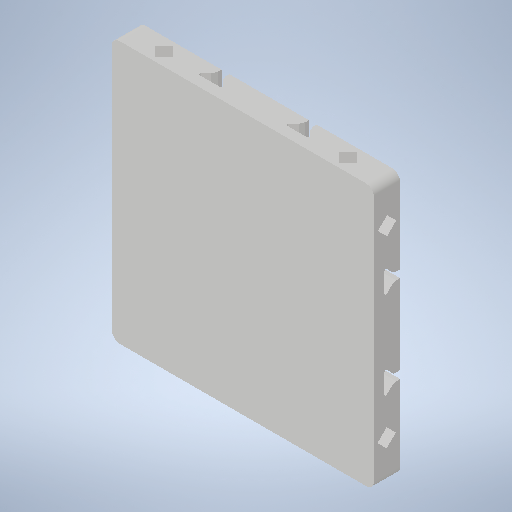
# Autodesk Inventor part: Main
Saved by Autodesk Inventor 2025.2 (Build 292293000, 293)
## iProperties
Created: 2026-02-04
Part Number: Main
Material: Generic
Document SubType Name: Modeling
Designer: crazi
Density: 1 g/cm^3
Appearance: Default
Author: crazi
Autodesk Inventor part; units mm, degrees
ref_plane "YZ Plane" through (0, 0, 0) normal (1, 0, 0) x (0, 1, 0)
sketch "Sketch1" plane through (0, 0, 0) normal (0, 0, 1) x (1, 0, 0)
  line L0 (0, 0) -> (100, 0)
  line L1 (100, 0) -> (100, -100)
  line L2 (100, -100) -> (0, -100)
  line L3 (0, -100) -> (0, 0)
  dimension "d0" = 100
  dimension "d1" = 100
  constraints: 8 end point, 2 parallel, 1 horizontal, 1 perpendicular
  measures "d0" distance of L1.end L2.end
  measures "d1" distance of L0.end L1.end
extrude "Extrusion1" add sketch "Sketch1" along normal blind 10
sketch "Sketch2" plane through (0, 0, 0) normal (0, 1, 0) x (1, 0, 0)
  line L0 (66.66, -6) -> (61.66, -6)
  line L1 (66.66, -6) -> (71.66, -6)
  line L2 (71.66, -6) -> (68.1245, -2.4645)
  line L3 (68.1245, -2.4645) -> (68.1245, 0)
  line L4 (61.66, -6) -> (65.1955, -2.4645)
  line L5 (61.66, -6) -> (66.66, -6) construction
  line L6 (65.1955, -2.4645) -> (65.1955, 0)
  line L7 (65.1955, 0) -> (68.1245, 0)
  line L8 (33.33, -6) -> (38.33, -6)
  line L9 (33.33, -6) -> (28.33, -6)
  line L10 (28.33, -6) -> (31.8655, -2.4645)
  line L11 (31.8655, -2.4645) -> (31.8655, 0)
  line L12 (38.33, -6) -> (34.7945, -2.4645)
  line L13 (38.33, -6) -> (43.33, -6) construction
  line L14 (34.7945, -2.4645) -> (34.7945, 0)
  line L15 (31.8655, 0) -> (34.7945, 0)
  line L16 (0, 0) -> (100, 0) projected
  dimension "d7" = 5
  dimension "d8" = 5
  dimension "d9" = 5
  dimension "d10" = 45
  dimension "d11" = 5
  dimension "d12" = 45
  dimension "d13" = 5
  dimension "d14" = 5
  dimension "d15" = 5
  dimension "d16" = 45
  dimension "d17" = 5
  dimension "d18" = 135
  constraints: 32 end point, 4 horizontal, 2 equal length, 2 perpendicular, 1 collinear
  measures "d7" distance of L0.start L0.end
  measures "d8" distance of L0.start L1.end
  measures "d9" distance of L1.end L2.end
  measures "d10" angle of L2 L1
  measures "d11" distance of L0.end L4.end
  measures "d12" angle of L5 L4
  measures "d13" distance of L8.start L8.end
  measures "d14" distance of L8.start L9.end
  measures "d15" distance of L9.end L10.end
  measures "d16" angle of L9 L10
  measures "d17" distance of L8.end L12.end
  measures "d18" angle of L13 L12
extrude "Extrusion2" cut sketch "Sketch2" against normal up to surface (100 mm away)
sketch "Sketch3" plane through (0, -100, 0) normal (-1, 0, 0) x (0, 0, 1)
  line L0 (0, 0) -> (2.4645, 0) projected
  line L1 (6, 33.33) -> (6, 38.33)
  line L2 (6, 33.33) -> (6, 28.33)
  line L3 (6, 28.33) -> (2.4645, 31.8655)
  line L4 (2.4645, 31.8655) -> (0, 31.8655)
  line L5 (6, 38.33) -> (2.4645, 34.7945)
  line L6 (6, 38.33) -> (11, 38.33) construction
  line L7 (2.4645, 34.7945) -> (0, 34.7945)
  line L8 (0, 31.8655) -> (0, 34.7945)
  line L9 (6, 66.66) -> (6, 61.66)
  line L10 (6, 61.66) -> (2.4645, 65.1955)
  line L11 (2.4645, 65.1955) -> (0, 65.1955)
  line L12 (6, 66.66) -> (6, 71.66)
  line L13 (6, 71.66) -> (2.4645, 68.1245)
  line L14 (2.4645, 68.1245) -> (0, 68.1245)
  line L15 (0, 65.1955) -> (0, 68.1245)
  point P0 (1.4645, 0)
  dimension "d30" = 5
  dimension "d31" = 5
  dimension "d32" = 5
  dimension "d33" = 45
  dimension "d34" = 5
  dimension "d35" = 135
  dimension "d36" = 5
  dimension "d37" = 5
  dimension "d38" = 45
  dimension "d39" = 5
  dimension "d40" = 5
  dimension "d41" = 45
  constraints: 30 end point, 1 equal length, 1 horizontal, 1 perpendicular
  measures "d30" distance of L1.start L1.end
  measures "d31" distance of L1.start L2.end
  measures "d32" distance of L2.end L3.end
  measures "d33" angle of L2 L3
  measures "d34" distance of L1.end L5.end
  measures "d35" angle of L5 L6
  measures "d36" distance of L9.start L9.end
  measures "d37" distance of L9.end L10.end
  measures "d38" angle of L9 L10
  measures "d39" distance of L9.start L12.end
  measures "d40" distance of L12.end L13.end
  measures "d41" angle of L13 L12
chamfer "Chamfer2" distance 1 angle 45 4 edges at (34.7945, -50, 2.4645) (68.1245, -50, 2.4645) (65.1955, -50, 2.4645) (31.8655, -50, 2.4645)
fillet "Fillet3" radius 0.5 4 edges at (28.33, -50, 6) (38.33, -50, 6) (71.66, -50, 6) (61.66, -50, 6)
extrude "Extrusion3" cut sketch "Sketch3" against normal up to surface (100 mm away)
chamfer "Chamfer3" distance 1 angle 45 11 edges at (15.7257, -34.8045, 2.4645) (15.7257, -68.1345, 2.4645) (15.7257, -65.2055, 2.4645) (15.7257, -31.8755, 2.4645) (84.2693, -34.8045, 2.4645) (84.2693, -68.1345, 2.4645) (49.995, -31.8755, 2.4645) (49.995, -68.1345, 2.4645) (49.995, -65.2055, 2.4645) (49.995, -34.8045, 2.4645) (84.2693, -31.8755, 2.4645)
fillet "Fillet4" radius 0.5 6 edges at (14.7686, -71.67, 6) (14.7686, -61.67, 6) (14.7686, -28.34, 6) (14.7686, -38.34, 6) (85.2264, -38.34, 6) (85.2264, -28.34, 6)
fillet "Fillet5" radius 0.5 6 edges at (85.2264, -71.67, 6) (85.2264, -61.67, 6) (49.995, -38.34, 6) (49.995, -28.34, 6) (49.995, -71.67, 6) (49.995, -61.67, 6)
sketch "Sketch4" plane through (0, -100, 10) normal (0, -1, 0) x (1, 0, 0)
  line L0 (85, -1.5) -> (88.5, -5)
  line L1 (88.5, -5) -> (85, -8.5)
  line L2 (85, -8.5) -> (81.5, -5)
  line L3 (81.5, -5) -> (85, -1.5)
  line L4 (15, -1.5) -> (18.5, -5)
  line L5 (18.5, -5) -> (15, -8.5)
  line L6 (15, -8.5) -> (11.5, -5)
  line L7 (11.5, -5) -> (15, -1.5)
  point P0 (0, -10)
  point P1 (15, -5)
  point P2 (100, -10)
  point P3 (85, -5)
  point P4 (85, -5)
  point P5 (15, -5)
  constraints: 16 end point, 2 coincident, 18 other
extrude "Extrusion4" cut sketch "Sketch4" against normal blind 11
sketch "Sketch5" plane through (100, -100, 10) normal (1, 0, 0) x (0, 0, -1)
  line L0 (1.3536, 15) -> (4.8536, 18.5)
  line L1 (4.8536, 18.5) -> (8.3536, 15)
  line L2 (8.3536, 15) -> (4.8536, 11.5)
  line L3 (4.8536, 11.5) -> (1.3536, 15)
  line L4 (1.5, 85) -> (5, 88.5)
  line L5 (5, 88.5) -> (8.5, 85)
  line L6 (8.5, 85) -> (5, 81.5)
  line L7 (5, 81.5) -> (1.5, 85)
  point P0 (0, 0)
  point P1 (4.8536, 15)
  point P2 (5, 85)
  point P3 (4.8536, 15)
  point P4 (5, 85)
  constraints: 16 end point, 2 coincident, 18 other
extrude "Extrusion5" cut sketch "Sketch5" against normal blind 11
ref_plane "Work Plane1" through (50, -100, 10) normal (-1, 0, 0) x (0, 0, 1)
ref_plane "Work Plane2" through (0, -50, 10) normal (0, -1, 0) x (1, 0, 0)
mirror "Mirror1" about plane through (0, -50, 10) normal (0, -1, 0) of "Extrusion4"
mirror "Mirror2" about plane through (50, -100, 10) normal (-1, 0, 0) of "Extrusion5"
chamfer "Chamfer4" distance 1 angle 45 32 edges at (86.75, -89, 6.75) (86.75, -89, 3.25) (83.25, -89, 3.25) (83.25, -89, 6.75) (13.25, -89, 3.25) (13.25, -89, 6.75) (16.75, -89, 3.25) (16.75, -89, 6.75) (13.25, -11, 3.25) (13.25, -11, 6.75) (16.75, -11, 3.25) (16.75, -11, 6.75) (83.25, -11, 3.25) (83.25, -11, 6.75) (86.75, -11, 6.75) (86.75, -11, 3.25) (89, -16.75, 6.75) (89, -16.75, 3.25) (89, -13.25, 3.25) (89, -13.25, 6.75) (89, -83.25, 3.3964) (89, -83.25, 6.8964) (89, -86.75, 6.8964) (89, -86.75, 3.3964) (11, -16.75, 6.75) (11, -16.75, 3.25) (11, -13.25, 3.25) (11, -13.25, 6.75) (11, -83.25, 3.3964) (11, -83.25, 6.8964) (11, -86.75, 3.3964) (11, -86.75, 6.8964)
fillet "Fillet6" radius 1 16 edges at (68.1245, -65.2055, 0.7322) (68.1245, -68.1345, 0.7322) (65.1955, -68.1345, 0.7322) (34.7945, -68.1345, 0.7322) (34.7945, -65.2055, 0.7322) (31.8655, -68.1345, 0.7322) (31.8655, -65.2055, 0.7322) (68.1245, -31.8755, 0.7322) (34.7945, -31.8755, 0.7322) (34.7945, -34.8045, 0.7322) (68.1245, -34.8045, 0.7322) (65.1955, -34.8045, 0.7322) (65.1955, -31.8755, 0.7322) (31.8655, -34.8045, 0.7322) (31.8655, -31.8755, 0.7322) (65.1955, -65.2055, 0.7322)
fillet "Fillet7" radius 3 4 edges at (0, -100, 5) (100, -100, 5) (100, 0, 5) (0, 0, 5)
body "Solid1"
